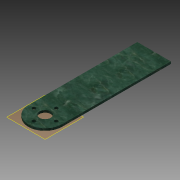
# Autodesk Inventor part: Yaw_Side
Saved by Autodesk Inventor 2013 (Build 170138000, 138)
## iProperties
Created: 2013-09-30
Part Number: Yaw_Side
Material: Generic
Document SubType Name: Modeling
Designer: Jeff
Density: 1 g/cm^3
Mass: 2.45792 g
Surface Area: 34.6846 cm^2
Volume: 2.45792 cm^3
Author: Jeff
Autodesk Inventor part; units mm, degrees
ref_plane "YZ Plane" through (0, 0, 0) normal (1, 0, 0) x (0, 1, 0)
ref_plane "XZ Plane" through (0, 0, 0) normal (0, 1, 0) x (-1, 0, 0)
ref_plane "XY Plane" through (0, 0, 0) normal (0, 0, 1) x (1, 0, 0)
ref_plane "Work Plane1" through (0, 0, 0) normal (0, 0, 1) x (1, 0, 0)
sketch "Sketch1" plane through (0, 0, 0) normal (0, 0, 1) x (1, 0, 0)
  line L0 (0, -12) -> (0, -12)
  line L1 (-12, 0) -> (-12, 78)
  line L2 (-12, 78) -> (12, 78)
  line L3 (12, 78) -> (12, 0)
  line L4 (0, 0) -> (0, 20.2388)
  arc A0 (-12, 0) -> (0, -12) centre (0, 0) ccw
  arc A1 (0, -12) -> (12, 0) centre (0, 0) ccw
  circle A2 centre (8, 0) radius 1.25
  circle A3 centre (0, 8) radius 1.25
  circle A4 centre (-8, 0) radius 1.25
  circle A5 centre (0, -8) radius 1.25
  circle A6 centre (0, 0) radius 4
  point P0 (0, 0)
  point P1 (-12, -12)
  dimension "d0" = 24
  dimension "d1" = 90
  dimension "d2" = 12
  dimension "d3" = 12
  dimension "d4" = 2.5
  dimension "d5" = 8
  dimension "d8" = 360
  dimension "d10" = 8
  constraints: 10 end point, 7 centre point, 4 point on circle, 4 tangent, 2 parallel, 2 point on line, 1 concentric, 1 horizontal, 1 perpendicular, 10 other
  measures "d0" distance of L1.end L2.end
  measures "d1" distance of point (-12, -12) L1.end
  measures "d2" distance from line of point (0, 0) L0
  measures "d3" radius of A0
  measures "d4" diameter of A2
  measures "d5" distance of point (0, 0) A2.centre
  measures "d10" diameter of A6
extrude "Extrusion1" add sketch "Sketch1" along normal blind 1.5875
equation "\"d2\" = 0.5 * d0"
equation "\"d3\" = 0.5 * d0"
body "Solid1"
